Autodesk Fusion 360 part; units mm, degrees
(part 4 of 7)
sketch "New stock profile (42)" plane through (330.6, 0, 0) normal (1, 0, 0) x (0, 0, -1) in component "front right rail mount 1-1 weld boss"
  circle A0 centre (-84.1, -195.15) radius 6.5
  circle A1 centre (-84.1, -195.15) radius 2.5
extrude "New 1'''''''''''''''''''''''''''''''''''''''''" add sketch "New stock profile (42)" against normal blind 16 separate body makes body 168 in component "front right rail mount 1-1 weld boss"
ref_plane "WorkPlane1" through (328.5, 0, 0) normal (1, 0, 0) x (0, 1, 0) in component "front right rail mount 1-1 M6 cap screw"
sketch "New stock profile (43)" plane through (328.5, 0, 0) normal (1, 0, 0) x (0, 0, -1) in component "front right rail mount 1-1 M6 cap screw"
  circle A0 centre (-84.1, -195.15) radius 3
extrude "New 1''''''''''''''''''''''''''''''''''''''''''" add sketch "New stock profile (43)" against normal blind 40 separate body makes body 169 in component "front right rail mount 1-1 M6 cap screw"
ref_plane "WorkPlane2" through (288.5, 0, 0) normal (1, 0, 0) x (0, 1, 0) in component "front right rail mount 1-1 M6 cap screw"
sketch "Join stock profile (9)" plane through (288.5, 0, 0) normal (1, 0, 0) x (0, 0, -1) in component "front right rail mount 1-1 M6 cap screw"
  circle A0 centre (-84.1, -195.15) radius 5
extrude "Join 2''''''''" add sketch "Join stock profile (9)" against normal blind 6 bodies 169 in component "front right rail mount 1-1 M6 cap screw"
ref_plane "WorkPlane3" through (282.49, 0, 0) normal (1, 0, 0) x (0, 1, 0) in component "front right rail mount 1-1 M6 cap screw"
sketch "Cut stock profile (33)" plane through (282.49, 0, 0) normal (1, 0, 0) x (0, 0, -1) in component "front right rail mount 1-1 M6 cap screw"
  line L0 (-84.1, -192.2632) -> (-86.6, -193.7066)
  line L1 (-86.6, -193.7066) -> (-86.6, -196.5934)
  line L2 (-86.6, -196.5934) -> (-84.1, -198.0368)
  line L3 (-84.1, -198.0368) -> (-81.6, -196.5934)
  line L4 (-81.6, -196.5934) -> (-81.6, -193.7066)
  line L5 (-81.6, -193.7066) -> (-84.1, -192.2632)
extrude "Cut 3''''''''''''''''" cut sketch "Cut stock profile (33)" along normal blind 3.01 bodies 169 in component "front right rail mount 1-1 M6 cap screw"
ref_plane "WorkPlane1" through (330.6, 0, 0) normal (1, 0, 0) x (0, 1, 0) in component "front right rail mount 1-2 weld boss"
sketch "New stock profile (44)" plane through (330.6, 0, 0) normal (1, 0, 0) x (0, 0, -1) in component "front right rail mount 1-2 weld boss"
  circle A0 centre (-105.1, -195.15) radius 6.5
  circle A1 centre (-105.1, -195.15) radius 2.5
extrude "New 1'''''''''''''''''''''''''''''''''''''''''''" add sketch "New stock profile (44)" against normal blind 16 separate body makes body 170 in component "front right rail mount 1-2 weld boss"
ref_plane "WorkPlane1" through (328.5, 0, 0) normal (1, 0, 0) x (0, 1, 0) in component "front right rail mount 1-2 M6 cap screw"
sketch "New stock profile (45)" plane through (328.5, 0, 0) normal (1, 0, 0) x (0, 0, -1) in component "front right rail mount 1-2 M6 cap screw"
  circle A0 centre (-105.1, -195.15) radius 3
extrude "New 1''''''''''''''''''''''''''''''''''''''''''''" add sketch "New stock profile (45)" against normal blind 40 separate body makes body 171 in component "front right rail mount 1-2 M6 cap screw"
ref_plane "WorkPlane2" through (288.5, 0, 0) normal (1, 0, 0) x (0, 1, 0) in component "front right rail mount 1-2 M6 cap screw"
sketch "Join stock profile (10)" plane through (288.5, 0, 0) normal (1, 0, 0) x (0, 0, -1) in component "front right rail mount 1-2 M6 cap screw"
  circle A0 centre (-105.1, -195.15) radius 5
extrude "Join 2'''''''''" add sketch "Join stock profile (10)" against normal blind 6 bodies 171 in component "front right rail mount 1-2 M6 cap screw"
ref_plane "WorkPlane3" through (282.49, 0, 0) normal (1, 0, 0) x (0, 1, 0) in component "front right rail mount 1-2 M6 cap screw"
sketch "Cut stock profile (34)" plane through (282.49, 0, 0) normal (1, 0, 0) x (0, 0, -1) in component "front right rail mount 1-2 M6 cap screw"
  line L0 (-105.1, -192.2632) -> (-107.6, -193.7066)
  line L1 (-107.6, -193.7066) -> (-107.6, -196.5934)
  line L2 (-107.6, -196.5934) -> (-105.1, -198.0368)
  line L3 (-105.1, -198.0368) -> (-102.6, -196.5934)
  line L4 (-102.6, -196.5934) -> (-102.6, -193.7066)
  line L5 (-102.6, -193.7066) -> (-105.1, -192.2632)
extrude "Cut 3'''''''''''''''''" cut sketch "Cut stock profile (34)" along normal blind 3.01 bodies 171 in component "front right rail mount 1-2 M6 cap screw"
ref_plane "WorkPlane1" through (0, 0, 65.5637) normal (0, 0, 1) x (1, 0, 0) in component "front right tab 1-1 socket screw"
sketch "New stock profile (46)" plane through (0, 0, 65.5637) normal (0, 0, 1) x (1, 0, 0) in component "front right tab 1-1 socket screw"
  circle A0 centre (296.75, -207.85) radius 2.413
extrude "New 1'''''''''''''''''''''''''''''''''''''''''''''" add sketch "New stock profile (46)" along normal blind 69.85 separate body makes body 172 in component "front right tab 1-1 socket screw"
ref_plane "WorkPlane2" through (0, 0, 60.7378) normal (0, 0, 1) x (1, 0, 0) in component "front right tab 1-1 socket screw"
sketch "Join stock profile (11)" plane through (0, 0, 60.7378) normal (0, 0, 1) x (1, 0, 0) in component "front right tab 1-1 socket screw"
  circle A0 centre (296.75, -207.85) radius 3.9624
extrude "Join 2''''''''''" add sketch "Join stock profile (11)" along normal blind 4.826 bodies 172 in component "front right tab 1-1 socket screw"
ref_plane "WorkPlane3" through (0, 0, 60.7278) normal (0, 0, 1) x (1, 0, 0) in component "front right tab 1-1 socket screw"
sketch "Cut stock profile (35)" plane through (0, 0, 60.7278) normal (0, 0, 1) x (1, 0, 0) in component "front right tab 1-1 socket screw"
  line L0 (299.0414, -207.85) -> (297.8957, -205.8656)
  line L1 (297.8957, -205.8656) -> (295.6043, -205.8656)
  line L2 (295.6043, -205.8656) -> (294.4586, -207.85)
  line L3 (294.4586, -207.85) -> (295.6043, -209.8344)
  line L4 (295.6043, -209.8344) -> (297.8957, -209.8344)
  line L5 (297.8957, -209.8344) -> (299.0414, -207.85)
extrude "Cut 3''''''''''''''''''" cut sketch "Cut stock profile (35)" along normal blind 2.296 bodies 172 in component "front right tab 1-1 socket screw"
ref_plane "WorkPlane1" through (0, 0, 124.3125) normal (0, 0, 1) x (1, 0, 0) in component "front right tab 1-1 locknut"
sketch "New stock profile (47)" plane through (0, 0, 124.3125) normal (0, 0, 1) x (1, 0, 0) in component "front right tab 1-1 locknut"
  line L0 (302.2639, -207.85) -> (299.507, -203.0748)
  line L1 (299.507, -203.0748) -> (293.993, -203.0748)
  line L2 (293.993, -203.0748) -> (291.2361, -207.85)
  line L3 (291.2361, -207.85) -> (293.993, -212.6252)
  line L4 (293.993, -212.6252) -> (299.507, -212.6252)
  line L5 (299.507, -212.6252) -> (302.2639, -207.85)
  circle A0 centre (296.75, -207.85) radius 2.43
extrude "New 1''''''''''''''''''''''''''''''''''''''''''''''" add sketch "New stock profile (47)" along normal blind 6.3246 separate body makes body 173 in component "front right tab 1-1 locknut"
ref_plane "WorkPlane1" through (0, 0, 65.5637) normal (0, 0, 1) x (1, 0, 0) in component "front right tab 1-2 socket screw"
sketch "New stock profile (48)" plane through (0, 0, 65.5637) normal (0, 0, 1) x (1, 0, 0) in component "front right tab 1-2 socket screw"
  circle A0 centre (296.75, -182.45) radius 2.413
extrude "New 1'''''''''''''''''''''''''''''''''''''''''''''''" add sketch "New stock profile (48)" along normal blind 69.85 separate body makes body 174 in component "front right tab 1-2 socket screw"
ref_plane "WorkPlane2" through (0, 0, 60.7378) normal (0, 0, 1) x (1, 0, 0) in component "front right tab 1-2 socket screw"
sketch "Join stock profile (12)" plane through (0, 0, 60.7378) normal (0, 0, 1) x (1, 0, 0) in component "front right tab 1-2 socket screw"
  circle A0 centre (296.75, -182.45) radius 3.9624
extrude "Join 2'''''''''''" add sketch "Join stock profile (12)" along normal blind 4.826 bodies 174 in component "front right tab 1-2 socket screw"
ref_plane "WorkPlane3" through (0, 0, 60.7278) normal (0, 0, 1) x (1, 0, 0) in component "front right tab 1-2 socket screw"
sketch "Cut stock profile (36)" plane through (0, 0, 60.7278) normal (0, 0, 1) x (1, 0, 0) in component "front right tab 1-2 socket screw"
  line L0 (299.0414, -182.45) -> (297.8957, -180.4656)
  line L1 (297.8957, -180.4656) -> (295.6043, -180.4656)
  line L2 (295.6043, -180.4656) -> (294.4586, -182.45)
  line L3 (294.4586, -182.45) -> (295.6043, -184.4344)
  line L4 (295.6043, -184.4344) -> (297.8957, -184.4344)
  line L5 (297.8957, -184.4344) -> (299.0414, -182.45)
extrude "Cut 3'''''''''''''''''''" cut sketch "Cut stock profile (36)" along normal blind 2.296 bodies 174 in component "front right tab 1-2 socket screw"
ref_plane "WorkPlane1" through (0, 0, 124.3125) normal (0, 0, 1) x (1, 0, 0) in component "front right tab 1-2 locknut"
sketch "New stock profile (49)" plane through (0, 0, 124.3125) normal (0, 0, 1) x (1, 0, 0) in component "front right tab 1-2 locknut"
  line L0 (302.2639, -182.45) -> (299.507, -177.6748)
  line L1 (299.507, -177.6748) -> (293.993, -177.6748)
  line L2 (293.993, -177.6748) -> (291.2361, -182.45)
  line L3 (291.2361, -182.45) -> (293.993, -187.2252)
  line L4 (293.993, -187.2252) -> (299.507, -187.2252)
  line L5 (299.507, -187.2252) -> (302.2639, -182.45)
  circle A0 centre (296.75, -182.45) radius 2.43
extrude "New 1''''''''''''''''''''''''''''''''''''''''''''''''" add sketch "New stock profile (49)" along normal blind 6.3246 separate body makes body 175 in component "front right tab 1-2 locknut"
ref_plane "WorkPlane1" through (0, -330.6, 0) normal (0, 1, 0) x (0, 0, 1) in component "front right rail mount 2-1 weld boss"
sketch "New stock profile (50)" plane through (0, -330.6, 0) normal (0, 1, 0) x (1, 0, 0) in component "front right rail mount 2-1 weld boss"
  circle A0 centre (195.15, -84.1) radius 6.5
  circle A1 centre (195.15, -84.1) radius 2.5
extrude "New 1'''''''''''''''''''''''''''''''''''''''''''''''''" add sketch "New stock profile (50)" along normal blind 16 separate body makes body 176 in component "front right rail mount 2-1 weld boss"
ref_plane "WorkPlane1" through (0, -328.5, 0) normal (0, 1, 0) x (0, 0, 1) in component "front right rail mount 2-1 M6 cap screw"
sketch "New stock profile (51)" plane through (0, -328.5, 0) normal (0, 1, 0) x (1, 0, 0) in component "front right rail mount 2-1 M6 cap screw"
  circle A0 centre (195.15, -84.1) radius 3
extrude "New 1''''''''''''''''''''''''''''''''''''''''''''''''''" add sketch "New stock profile (51)" along normal blind 40 separate body makes body 177 in component "front right rail mount 2-1 M6 cap screw"
ref_plane "WorkPlane2" through (0, -288.5, 0) normal (0, 1, 0) x (0, 0, 1) in component "front right rail mount 2-1 M6 cap screw"
sketch "Join stock profile (13)" plane through (0, -288.5, 0) normal (0, 1, 0) x (1, 0, 0) in component "front right rail mount 2-1 M6 cap screw"
  circle A0 centre (195.15, -84.1) radius 5
extrude "Join 2''''''''''''" add sketch "Join stock profile (13)" along normal blind 6 bodies 177 in component "front right rail mount 2-1 M6 cap screw"
ref_plane "WorkPlane3" through (0, -282.49, 0) normal (0, 1, 0) x (0, 0, 1) in component "front right rail mount 2-1 M6 cap screw"
sketch "Cut stock profile (37)" plane through (0, -282.49, 0) normal (0, 1, 0) x (1, 0, 0) in component "front right rail mount 2-1 M6 cap screw"
  line L0 (198.0368, -84.1) -> (196.5934, -86.6)
  line L1 (196.5934, -86.6) -> (193.7066, -86.6)
  line L2 (193.7066, -86.6) -> (192.2632, -84.1)
  line L3 (192.2632, -84.1) -> (193.7066, -81.6)
  line L4 (193.7066, -81.6) -> (196.5934, -81.6)
  line L5 (196.5934, -81.6) -> (198.0368, -84.1)
extrude "Cut 3''''''''''''''''''''" cut sketch "Cut stock profile (37)" against normal blind 3.01 bodies 177 in component "front right rail mount 2-1 M6 cap screw"
ref_plane "WorkPlane1" through (0, -330.6, 0) normal (0, 1, 0) x (0, 0, 1) in component "front right rail mount 2-2 weld boss"
sketch "New stock profile (52)" plane through (0, -330.6, 0) normal (0, 1, 0) x (1, 0, 0) in component "front right rail mount 2-2 weld boss"
  circle A0 centre (195.15, -105.1) radius 6.5
  circle A1 centre (195.15, -105.1) radius 2.5
extrude "New 1'''''''''''''''''''''''''''''''''''''''''''''''''''" add sketch "New stock profile (52)" along normal blind 16 separate body makes body 178 in component "front right rail mount 2-2 weld boss"
ref_plane "WorkPlane1" through (0, -328.5, 0) normal (0, 1, 0) x (0, 0, 1) in component "front right rail mount 2-2 M6 cap screw"
sketch "New stock profile (53)" plane through (0, -328.5, 0) normal (0, 1, 0) x (1, 0, 0) in component "front right rail mount 2-2 M6 cap screw"
  circle A0 centre (195.15, -105.1) radius 3
extrude "New 1''''''''''''''''''''''''''''''''''''''''''''''''''''" add sketch "New stock profile (53)" along normal blind 40 separate body makes body 179 in component "front right rail mount 2-2 M6 cap screw"
ref_plane "WorkPlane2" through (0, -288.5, 0) normal (0, 1, 0) x (0, 0, 1) in component "front right rail mount 2-2 M6 cap screw"
sketch "Join stock profile (14)" plane through (0, -288.5, 0) normal (0, 1, 0) x (1, 0, 0) in component "front right rail mount 2-2 M6 cap screw"
  circle A0 centre (195.15, -105.1) radius 5
extrude "Join 2'''''''''''''" add sketch "Join stock profile (14)" along normal blind 6 bodies 179 in component "front right rail mount 2-2 M6 cap screw"
ref_plane "WorkPlane3" through (0, -282.49, 0) normal (0, 1, 0) x (0, 0, 1) in component "front right rail mount 2-2 M6 cap screw"
sketch "Cut stock profile (38)" plane through (0, -282.49, 0) normal (0, 1, 0) x (1, 0, 0) in component "front right rail mount 2-2 M6 cap screw"
  line L0 (198.0368, -105.1) -> (196.5934, -107.6)
  line L1 (196.5934, -107.6) -> (193.7066, -107.6)
  line L2 (193.7066, -107.6) -> (192.2632, -105.1)
  line L3 (192.2632, -105.1) -> (193.7066, -102.6)
  line L4 (193.7066, -102.6) -> (196.5934, -102.6)
  line L5 (196.5934, -102.6) -> (198.0368, -105.1)
extrude "Cut 3'''''''''''''''''''''" cut sketch "Cut stock profile (38)" against normal blind 3.01 bodies 179 in component "front right rail mount 2-2 M6 cap screw"
ref_plane "WorkPlane1" through (0, 0, 65.5637) normal (0, 0, 1) x (1, 0, 0) in component "front right tab 2-1 socket screw"
sketch "New stock profile (54)" plane through (0, 0, 65.5637) normal (0, 0, 1) x (1, 0, 0) in component "front right tab 2-1 socket screw"
  circle A0 centre (207.85, -296.75) radius 2.413
extrude "New 1'''''''''''''''''''''''''''''''''''''''''''''''''''''" add sketch "New stock profile (54)" along normal blind 69.85 separate body makes body 180 in component "front right tab 2-1 socket screw"
ref_plane "WorkPlane2" through (0, 0, 60.7378) normal (0, 0, 1) x (1, 0, 0) in component "front right tab 2-1 socket screw"
sketch "Join stock profile (15)" plane through (0, 0, 60.7378) normal (0, 0, 1) x (1, 0, 0) in component "front right tab 2-1 socket screw"
  circle A0 centre (207.85, -296.75) radius 3.9624
extrude "Join 2''''''''''''''" add sketch "Join stock profile (15)" along normal blind 4.826 bodies 180 in component "front right tab 2-1 socket screw"
ref_plane "WorkPlane3" through (0, 0, 60.7278) normal (0, 0, 1) x (1, 0, 0) in component "front right tab 2-1 socket screw"
sketch "Cut stock profile (39)" plane through (0, 0, 60.7278) normal (0, 0, 1) x (1, 0, 0) in component "front right tab 2-1 socket screw"
  line L0 (210.1414, -296.75) -> (208.9957, -294.7656)
  line L1 (208.9957, -294.7656) -> (206.7043, -294.7656)
  line L2 (206.7043, -294.7656) -> (205.5586, -296.75)
  line L3 (205.5586, -296.75) -> (206.7043, -298.7344)
  line L4 (206.7043, -298.7344) -> (208.9957, -298.7344)
  line L5 (208.9957, -298.7344) -> (210.1414, -296.75)
extrude "Cut 3''''''''''''''''''''''" cut sketch "Cut stock profile (39)" along normal blind 2.296 bodies 180 in component "front right tab 2-1 socket screw"
ref_plane "WorkPlane1" through (0, 0, 124.3125) normal (0, 0, 1) x (1, 0, 0) in component "front right tab 2-1 locknut"
sketch "New stock profile (55)" plane through (0, 0, 124.3125) normal (0, 0, 1) x (1, 0, 0) in component "front right tab 2-1 locknut"
  line L0 (213.3639, -296.75) -> (210.607, -291.9748)
  line L1 (210.607, -291.9748) -> (205.093, -291.9748)
  line L2 (205.093, -291.9748) -> (202.3361, -296.75)
  line L3 (202.3361, -296.75) -> (205.093, -301.5252)
  line L4 (205.093, -301.5252) -> (210.607, -301.5252)
  line L5 (210.607, -301.5252) -> (213.3639, -296.75)
  circle A0 centre (207.85, -296.75) radius 2.43
extrude "New 1''''''''''''''''''''''''''''''''''''''''''''''''''''''" add sketch "New stock profile (55)" along normal blind 6.3246 separate body makes body 181 in component "front right tab 2-1 locknut"
ref_plane "WorkPlane1" through (0, 0, 65.5637) normal (0, 0, 1) x (1, 0, 0) in component "front right tab 2-2 socket screw"
sketch "New stock profile (56)" plane through (0, 0, 65.5637) normal (0, 0, 1) x (1, 0, 0) in component "front right tab 2-2 socket screw"
  circle A0 centre (182.45, -296.75) radius 2.413
extrude "New 1'''''''''''''''''''''''''''''''''''''''''''''''''''''''" add sketch "New stock profile (56)" along normal blind 69.85 separate body makes body 182 in component "front right tab 2-2 socket screw"
ref_plane "WorkPlane2" through (0, 0, 60.7378) normal (0, 0, 1) x (1, 0, 0) in component "front right tab 2-2 socket screw"
sketch "Join stock profile (16)" plane through (0, 0, 60.7378) normal (0, 0, 1) x (1, 0, 0) in component "front right tab 2-2 socket screw"
  circle A0 centre (182.45, -296.75) radius 3.9624
extrude "Join 2'''''''''''''''" add sketch "Join stock profile (16)" along normal blind 4.826 bodies 182 in component "front right tab 2-2 socket screw"
ref_plane "WorkPlane3" through (0, 0, 60.7278) normal (0, 0, 1) x (1, 0, 0) in component "front right tab 2-2 socket screw"
sketch "Cut stock profile (40)" plane through (0, 0, 60.7278) normal (0, 0, 1) x (1, 0, 0) in component "front right tab 2-2 socket screw"
  line L0 (184.7414, -296.75) -> (183.5957, -294.7656)
  line L1 (183.5957, -294.7656) -> (181.3043, -294.7656)
  line L2 (181.3043, -294.7656) -> (180.1586, -296.75)
  line L3 (180.1586, -296.75) -> (181.3043, -298.7344)
  line L4 (181.3043, -298.7344) -> (183.5957, -298.7344)
  line L5 (183.5957, -298.7344) -> (184.7414, -296.75)
extrude "Cut 3'''''''''''''''''''''''" cut sketch "Cut stock profile (40)" along normal blind 2.296 bodies 182 in component "front right tab 2-2 socket screw"
ref_plane "WorkPlane1" through (0, 0, 124.3125) normal (0, 0, 1) x (1, 0, 0) in component "front right tab 2-2 locknut"
sketch "New stock profile (57)" plane through (0, 0, 124.3125) normal (0, 0, 1) x (1, 0, 0) in component "front right tab 2-2 locknut"
  line L0 (187.9639, -296.75) -> (185.207, -291.9748)
  line L1 (185.207, -291.9748) -> (179.693, -291.9748)
  line L2 (179.693, -291.9748) -> (176.9361, -296.75)
  line L3 (176.9361, -296.75) -> (179.693, -301.5252)
  line L4 (179.693, -301.5252) -> (185.207, -301.5252)
  line L5 (185.207, -301.5252) -> (187.9639, -296.75)
  circle A0 centre (182.45, -296.75) radius 2.43
extrude "New 1''''''''''''''''''''''''''''''''''''''''''''''''''''''''" add sketch "New stock profile (57)" along normal blind 6.3246 separate body makes body 183 in component "front right tab 2-2 locknut"
ref_plane "WorkPlane1" through (-330.6, 0, 0) normal (1, 0, 0) x (0, 1, 0) in component "rear left rail mount 1-1 weld boss"
sketch "New stock profile (58)" plane through (-330.6, 0, 0) normal (1, 0, 0) x (0, 0, -1) in component "rear left rail mount 1-1 weld boss"
  circle A0 centre (-84.1, 195.15) radius 6.5
  circle A1 centre (-84.1, 195.15) radius 2.5
extrude "New 1'''''''''''''''''''''''''''''''''''''''''''''''''''''''''" add sketch "New stock profile (58)" along normal blind 16 separate body makes body 184 in component "rear left rail mount 1-1 weld boss"
ref_plane "WorkPlane1" through (-328.5, 0, 0) normal (1, 0, 0) x (0, 1, 0) in component "rear left rail mount 1-1 M6 cap screw"
sketch "New stock profile (59)" plane through (-328.5, 0, 0) normal (1, 0, 0) x (0, 0, -1) in component "rear left rail mount 1-1 M6 cap screw"
  circle A0 centre (-84.1, 195.15) radius 3
extrude "New 1''''''''''''''''''''''''''''''''''''''''''''''''''''''''''" add sketch "New stock profile (59)" along normal blind 40 separate body makes body 185 in component "rear left rail mount 1-1 M6 cap screw"
ref_plane "WorkPlane2" through (-288.5, 0, 0) normal (1, 0, 0) x (0, 1, 0) in component "rear left rail mount 1-1 M6 cap screw"
sketch "Join stock profile (17)" plane through (-288.5, 0, 0) normal (1, 0, 0) x (0, 0, -1) in component "rear left rail mount 1-1 M6 cap screw"
  circle A0 centre (-84.1, 195.15) radius 5
extrude "Join 2''''''''''''''''" add sketch "Join stock profile (17)" along normal blind 6 bodies 185 in component "rear left rail mount 1-1 M6 cap screw"
ref_plane "WorkPlane3" through (-282.49, 0, 0) normal (1, 0, 0) x (0, 1, 0) in component "rear left rail mount 1-1 M6 cap screw"
sketch "Cut stock profile (41)" plane through (-282.49, 0, 0) normal (1, 0, 0) x (0, 0, -1) in component "rear left rail mount 1-1 M6 cap screw"
  line L0 (-84.1, 192.2632) -> (-86.6, 193.7066)
  line L1 (-86.6, 193.7066) -> (-86.6, 196.5934)
  line L2 (-86.6, 196.5934) -> (-84.1, 198.0368)
  line L3 (-84.1, 198.0368) -> (-81.6, 196.5934)
  line L4 (-81.6, 196.5934) -> (-81.6, 193.7066)
  line L5 (-81.6, 193.7066) -> (-84.1, 192.2632)
extrude "Cut 3''''''''''''''''''''''''" cut sketch "Cut stock profile (41)" against normal blind 3.01 bodies 185 in component "rear left rail mount 1-1 M6 cap screw"
ref_plane "WorkPlane1" through (-330.6, 0, 0) normal (1, 0, 0) x (0, 1, 0) in component "rear left rail mount 1-2 weld boss"
sketch "New stock profile (60)" plane through (-330.6, 0, 0) normal (1, 0, 0) x (0, 0, -1) in component "rear left rail mount 1-2 weld boss"
  circle A0 centre (-105.1, 195.15) radius 6.5
  circle A1 centre (-105.1, 195.15) radius 2.5
extrude "New 1'''''''''''''''''''''''''''''''''''''''''''''''''''''''''''" add sketch "New stock profile (60)" along normal blind 16 separate body makes body 186 in component "rear left rail mount 1-2 weld boss"
ref_plane "WorkPlane1" through (-328.5, 0, 0) normal (1, 0, 0) x (0, 1, 0) in component "rear left rail mount 1-2 M6 cap screw"
sketch "New stock profile (61)" plane through (-328.5, 0, 0) normal (1, 0, 0) x (0, 0, -1) in component "rear left rail mount 1-2 M6 cap screw"
  circle A0 centre (-105.1, 195.15) radius 3
extrude "New 1''''''''''''''''''''''''''''''''''''''''''''''''''''''''''''" add sketch "New stock profile (61)" along normal blind 40 separate body makes body 187 in component "rear left rail mount 1-2 M6 cap screw"
ref_plane "WorkPlane2" through (-288.5, 0, 0) normal (1, 0, 0) x (0, 1, 0) in component "rear left rail mount 1-2 M6 cap screw"
sketch "Join stock profile (18)" plane through (-288.5, 0, 0) normal (1, 0, 0) x (0, 0, -1) in component "rear left rail mount 1-2 M6 cap screw"
  circle A0 centre (-105.1, 195.15) radius 5
extrude "Join 2'''''''''''''''''" add sketch "Join stock profile (18)" along normal blind 6 bodies 187 in component "rear left rail mount 1-2 M6 cap screw"
ref_plane "WorkPlane3" through (-282.49, 0, 0) normal (1, 0, 0) x (0, 1, 0) in component "rear left rail mount 1-2 M6 cap screw"
sketch "Cut stock profile (42)" plane through (-282.49, 0, 0) normal (1, 0, 0) x (0, 0, -1) in component "rear left rail mount 1-2 M6 cap screw"
  line L0 (-105.1, 192.2632) -> (-107.6, 193.7066)
  line L1 (-107.6, 193.7066) -> (-107.6, 196.5934)
  line L2 (-107.6, 196.5934) -> (-105.1, 198.0368)
  line L3 (-105.1, 198.0368) -> (-102.6, 196.5934)
  line L4 (-102.6, 196.5934) -> (-102.6, 193.7066)
  line L5 (-102.6, 193.7066) -> (-105.1, 192.2632)
extrude "Cut 3'''''''''''''''''''''''''" cut sketch "Cut stock profile (42)" against normal blind 3.01 bodies 187 in component "rear left rail mount 1-2 M6 cap screw"
ref_plane "WorkPlane1" through (0, 0, 65.5637) normal (0, 0, 1) x (1, 0, 0) in component "rear left tab 1-1 socket screw"
sketch "New stock profile (62)" plane through (0, 0, 65.5637) normal (0, 0, 1) x (1, 0, 0) in component "rear left tab 1-1 socket screw"
  circle A0 centre (-296.75, 207.85) radius 2.413
extrude "New 1'''''''''''''''''''''''''''''''''''''''''''''''''''''''''''''" add sketch "New stock profile (62)" along normal blind 69.85 separate body makes body 188 in component "rear left tab 1-1 socket screw"
ref_plane "WorkPlane2" through (0, 0, 60.7378) normal (0, 0, 1) x (1, 0, 0) in component "rear left tab 1-1 socket screw"
sketch "Join stock profile (19)" plane through (0, 0, 60.7378) normal (0, 0, 1) x (1, 0, 0) in component "rear left tab 1-1 socket screw"
  circle A0 centre (-296.75, 207.85) radius 3.9624
extrude "Join 2''''''''''''''''''" add sketch "Join stock profile (19)" along normal blind 4.826 bodies 188 in component "rear left tab 1-1 socket screw"
ref_plane "WorkPlane3" through (0, 0, 60.7278) normal (0, 0, 1) x (1, 0, 0) in component "rear left tab 1-1 socket screw"
sketch "Cut stock profile (43)" plane through (0, 0, 60.7278) normal (0, 0, 1) x (1, 0, 0) in component "rear left tab 1-1 socket screw"
  line L0 (-294.4586, 207.85) -> (-295.6043, 209.8344)
  line L1 (-295.6043, 209.8344) -> (-297.8957, 209.8344)
  line L2 (-297.8957, 209.8344) -> (-299.0414, 207.85)
  line L3 (-299.0414, 207.85) -> (-297.8957, 205.8656)
  line L4 (-297.8957, 205.8656) -> (-295.6043, 205.8656)
  line L5 (-295.6043, 205.8656) -> (-294.4586, 207.85)
extrude "Cut 3''''''''''''''''''''''''''" cut sketch "Cut stock profile (43)" along normal blind 2.296 bodies 188 in component "rear left tab 1-1 socket screw"
ref_plane "WorkPlane1" through (0, 0, 124.3125) normal (0, 0, 1) x (1, 0, 0) in component "rear left tab 1-1 locknut"
sketch "New stock profile (63)" plane through (0, 0, 124.3125) normal (0, 0, 1) x (1, 0, 0) in component "rear left tab 1-1 locknut"
  line L0 (-291.2361, 207.85) -> (-293.993, 212.6252)
  line L1 (-293.993, 212.6252) -> (-299.507, 212.6252)
  line L2 (-299.507, 212.6252) -> (-302.2639, 207.85)
  line L3 (-302.2639, 207.85) -> (-299.507, 203.0748)
  line L4 (-299.507, 203.0748) -> (-293.993, 203.0748)
  line L5 (-293.993, 203.0748) -> (-291.2361, 207.85)
  circle A0 centre (-296.75, 207.85) radius 2.43
extrude "New 1''''''''''''''''''''''''''''''''''''''''''''''''''''''''''''''" add sketch "New stock profile (63)" along normal blind 6.3246 separate body makes body 189 in component "rear left tab 1-1 locknut"
ref_plane "WorkPlane1" through (0, 0, 65.5637) normal (0, 0, 1) x (1, 0, 0) in component "rear left tab 1-2 socket screw"
sketch "New stock profile (64)" plane through (0, 0, 65.5637) normal (0, 0, 1) x (1, 0, 0) in component "rear left tab 1-2 socket screw"
  circle A0 centre (-296.75, 182.45) radius 2.413
extrude "New 1'''''''''''''''''''''''''''''''''''''''''''''''''''''''''''''''" add sketch "New stock profile (64)" along normal blind 69.85 separate body makes body 190 in component "rear left tab 1-2 socket screw"
ref_plane "WorkPlane2" through (0, 0, 60.7378) normal (0, 0, 1) x (1, 0, 0) in component "rear left tab 1-2 socket screw"
sketch "Join stock profile (20)" plane through (0, 0, 60.7378) normal (0, 0, 1) x (1, 0, 0) in component "rear left tab 1-2 socket screw"
  circle A0 centre (-296.75, 182.45) radius 3.9624
extrude "Join 2'''''''''''''''''''" add sketch "Join stock profile (20)" along normal blind 4.826 bodies 190 in component "rear left tab 1-2 socket screw"
ref_plane "WorkPlane3" through (0, 0, 60.7278) normal (0, 0, 1) x (1, 0, 0) in component "rear left tab 1-2 socket screw"
sketch "Cut stock profile (44)" plane through (0, 0, 60.7278) normal (0, 0, 1) x (1, 0, 0) in component "rear left tab 1-2 socket screw"
  line L0 (-294.4586, 182.45) -> (-295.6043, 184.4344)
  line L1 (-295.6043, 184.4344) -> (-297.8957, 184.4344)
  line L2 (-297.8957, 184.4344) -> (-299.0414, 182.45)
  line L3 (-299.0414, 182.45) -> (-297.8957, 180.4656)
  line L4 (-297.8957, 180.4656) -> (-295.6043, 180.4656)
  line L5 (-295.6043, 180.4656) -> (-294.4586, 182.45)
extrude "Cut 3'''''''''''''''''''''''''''" cut sketch "Cut stock profile (44)" along normal blind 2.296 bodies 190 in component "rear left tab 1-2 socket screw"
ref_plane "WorkPlane1" through (0, 0, 124.3125) normal (0, 0, 1) x (1, 0, 0) in component "rear left tab 1-2 locknut"
sketch "New stock profile (65)" plane through (0, 0, 124.3125) normal (0, 0, 1) x (1, 0, 0) in component "rear left tab 1-2 locknut"
  line L0 (-291.2361, 182.45) -> (-293.993, 187.2252)
  line L1 (-293.993, 187.2252) -> (-299.507, 187.2252)
  line L2 (-299.507, 187.2252) -> (-302.2639, 182.45)
  line L3 (-302.2639, 182.45) -> (-299.507, 177.6748)
  line L4 (-299.507, 177.6748) -> (-293.993, 177.6748)
  line L5 (-293.993, 177.6748) -> (-291.2361, 182.45)
  circle A0 centre (-296.75, 182.45) radius 2.43
extrude "New 1''''''''''''''''''''''''''''''''''''''''''''''''''''''''''''''''" add sketch "New stock profile (65)" along normal blind 6.3246 separate body makes body 191 in component "rear left tab 1-2 locknut"
ref_plane "WorkPlane1" through (0, 330.6, 0) normal (0, 1, 0) x (0, 0, 1) in component "rear left rail mount 2-1 weld boss"
sketch "New stock profile (66)" plane through (0, 330.6, 0) normal (0, 1, 0) x (1, 0, 0) in component "rear left rail mount 2-1 weld boss"
  circle A0 centre (-195.15, -84.1) radius 6.5
  circle A1 centre (-195.15, -84.1) radius 2.5
extrude "New 1'''''''''''''''''''''''''''''''''''''''''''''''''''''''''''''''''" add sketch "New stock profile (66)" against normal blind 16 separate body makes body 192 in component "rear left rail mount 2-1 weld boss"
ref_plane "WorkPlane1" through (0, 328.5, 0) normal (0, 1, 0) x (0, 0, 1) in component "rear left rail mount 2-1 M6 cap screw"
sketch "New stock profile (67)" plane through (0, 328.5, 0) normal (0, 1, 0) x (1, 0, 0) in component "rear left rail mount 2-1 M6 cap screw"
  circle A0 centre (-195.15, -84.1) radius 3
extrude "New 1''''''''''''''''''''''''''''''''''''''''''''''''''''''''''''''''''" add sketch "New stock profile (67)" against normal blind 40 separate body makes body 193 in component "rear left rail mount 2-1 M6 cap screw"
ref_plane "WorkPlane2" through (0, 288.5, 0) normal (0, 1, 0) x (0, 0, 1) in component "rear left rail mount 2-1 M6 cap screw"
sketch "Join stock profile (21)" plane through (0, 288.5, 0) normal (0, 1, 0) x (1, 0, 0) in component "rear left rail mount 2-1 M6 cap screw"
  circle A0 centre (-195.15, -84.1) radius 5
extrude "Join 2''''''''''''''''''''" add sketch "Join stock profile (21)" against normal blind 6 bodies 193 in component "rear left rail mount 2-1 M6 cap screw"
ref_plane "WorkPlane3" through (0, 282.49, 0) normal (0, 1, 0) x (0, 0, 1) in component "rear left rail mount 2-1 M6 cap screw"
sketch "Cut stock profile (45)" plane through (0, 282.49, 0) normal (0, 1, 0) x (1, 0, 0) in component "rear left rail mount 2-1 M6 cap screw"
  line L0 (-198.0368, -84.1) -> (-196.5934, -86.6)
  line L1 (-196.5934, -86.6) -> (-193.7066, -86.6)
  line L2 (-193.7066, -86.6) -> (-192.2632, -84.1)
  line L3 (-192.2632, -84.1) -> (-193.7066, -81.6)
  line L4 (-193.7066, -81.6) -> (-196.5934, -81.6)
  line L5 (-196.5934, -81.6) -> (-198.0368, -84.1)
extrude "Cut 3''''''''''''''''''''''''''''" cut sketch "Cut stock profile (45)" along normal blind 3.01 bodies 193 in component "rear left rail mount 2-1 M6 cap screw"
ref_plane "WorkPlane1" through (0, 330.6, 0) normal (0, 1, 0) x (0, 0, 1) in component "rear left rail mount 2-2 weld boss"
sketch "New stock profile (68)" plane through (0, 330.6, 0) normal (0, 1, 0) x (1, 0, 0) in component "rear left rail mount 2-2 weld boss"
  circle A0 centre (-195.15, -105.1) radius 6.5
  circle A1 centre (-195.15, -105.1) radius 2.5
extrude "New 1'''''''''''''''''''''''''''''''''''''''''''''''''''''''''''''''''''" add sketch "New stock profile (68)" against normal blind 16 separate body makes body 194 in component "rear left rail mount 2-2 weld boss"
ref_plane "WorkPlane1" through (0, 328.5, 0) normal (0, 1, 0) x (0, 0, 1) in component "rear left rail mount 2-2 M6 cap screw"
sketch "New stock profile (69)" plane through (0, 328.5, 0) normal (0, 1, 0) x (1, 0, 0) in component "rear left rail mount 2-2 M6 cap screw"
  circle A0 centre (-195.15, -105.1) radius 3
extrude "New 1''''''''''''''''''''''''''''''''''''''''''''''''''''''''''''''''''''" add sketch "New stock profile (69)" against normal blind 40 separate body makes body 195 in component "rear left rail mount 2-2 M6 cap screw"
ref_plane "WorkPlane2" through (0, 288.5, 0) normal (0, 1, 0) x (0, 0, 1) in component "rear left rail mount 2-2 M6 cap screw"
sketch "Join stock profile (22)" plane through (0, 288.5, 0) normal (0, 1, 0) x (1, 0, 0) in component "rear left rail mount 2-2 M6 cap screw"
  circle A0 centre (-195.15, -105.1) radius 5
extrude "Join 2'''''''''''''''''''''" add sketch "Join stock profile (22)" against normal blind 6 bodies 195 in component "rear left rail mount 2-2 M6 cap screw"
ref_plane "WorkPlane3" through (0, 282.49, 0) normal (0, 1, 0) x (0, 0, 1) in component "rear left rail mount 2-2 M6 cap screw"
sketch "Cut stock profile (46)" plane through (0, 282.49, 0) normal (0, 1, 0) x (1, 0, 0) in component "rear left rail mount 2-2 M6 cap screw"
  line L0 (-198.0368, -105.1) -> (-196.5934, -107.6)
  line L1 (-196.5934, -107.6) -> (-193.7066, -107.6)
  line L2 (-193.7066, -107.6) -> (-192.2632, -105.1)
  line L3 (-192.2632, -105.1) -> (-193.7066, -102.6)
  line L4 (-193.7066, -102.6) -> (-196.5934, -102.6)
  line L5 (-196.5934, -102.6) -> (-198.0368, -105.1)
extrude "Cut 3'''''''''''''''''''''''''''''" cut sketch "Cut stock profile (46)" along normal blind 3.01 bodies 195 in component "rear left rail mount 2-2 M6 cap screw"
ref_plane "WorkPlane1" through (0, 0, 65.5637) normal (0, 0, 1) x (1, 0, 0) in component "rear left tab 2-1 socket screw"
sketch "New stock profile (70)" plane through (0, 0, 65.5637) normal (0, 0, 1) x (1, 0, 0) in component "rear left tab 2-1 socket screw"
  circle A0 centre (-207.85, 296.75) radius 2.413
extrude "New 1'''''''''''''''''''''''''''''''''''''''''''''''''''''''''''''''''''''" add sketch "New stock profile (70)" along normal blind 69.85 separate body makes body 196 in component "rear left tab 2-1 socket screw"
ref_plane "WorkPlane2" through (0, 0, 60.7378) normal (0, 0, 1) x (1, 0, 0) in component "rear left tab 2-1 socket screw"
sketch "Join stock profile (23)" plane through (0, 0, 60.7378) normal (0, 0, 1) x (1, 0, 0) in component "rear left tab 2-1 socket screw"
  circle A0 centre (-207.85, 296.75) radius 3.9624
extrude "Join 2''''''''''''''''''''''" add sketch "Join stock profile (23)" along normal blind 4.826 bodies 196 in component "rear left tab 2-1 socket screw"
ref_plane "WorkPlane3" through (0, 0, 60.7278) normal (0, 0, 1) x (1, 0, 0) in component "rear left tab 2-1 socket screw"
sketch "Cut stock profile (47)" plane through (0, 0, 60.7278) normal (0, 0, 1) x (1, 0, 0) in component "rear left tab 2-1 socket screw"
  line L0 (-205.5586, 296.75) -> (-206.7043, 298.7344)
  line L1 (-206.7043, 298.7344) -> (-208.9957, 298.7344)
  line L2 (-208.9957, 298.7344) -> (-210.1414, 296.75)
  line L3 (-210.1414, 296.75) -> (-208.9957, 294.7656)
  line L4 (-208.9957, 294.7656) -> (-206.7043, 294.7656)
  line L5 (-206.7043, 294.7656) -> (-205.5586, 296.75)
extrude "Cut 3''''''''''''''''''''''''''''''" cut sketch "Cut stock profile (47)" along normal blind 2.296 bodies 196 in component "rear left tab 2-1 socket screw"
ref_plane "WorkPlane1" through (0, 0, 124.3125) normal (0, 0, 1) x (1, 0, 0) in component "rear left tab 2-1 locknut"
sketch "New stock profile (71)" plane through (0, 0, 124.3125) normal (0, 0, 1) x (1, 0, 0) in component "rear left tab 2-1 locknut"
  line L0 (-202.3361, 296.75) -> (-205.093, 301.5252)
  line L1 (-205.093, 301.5252) -> (-210.607, 301.5252)
  line L2 (-210.607, 301.5252) -> (-213.3639, 296.75)
  line L3 (-213.3639, 296.75) -> (-210.607, 291.9748)
  line L4 (-210.607, 291.9748) -> (-205.093, 291.9748)
  line L5 (-205.093, 291.9748) -> (-202.3361, 296.75)
  circle A0 centre (-207.85, 296.75) radius 2.43
extrude "New 1''''''''''''''''''''''''''''''''''''''''''''''''''''''''''''''''''''''" add sketch "New stock profile (71)" along normal blind 6.3246 separate body makes body 197 in component "rear left tab 2-1 locknut"
ref_plane "WorkPlane1" through (0, 0, 65.5637) normal (0, 0, 1) x (1, 0, 0) in component "rear left tab 2-2 socket screw"
sketch "New stock profile (72)" plane through (0, 0, 65.5637) normal (0, 0, 1) x (1, 0, 0) in component "rear left tab 2-2 socket screw"
  circle A0 centre (-182.45, 296.75) radius 2.413
extrude "New 1'''''''''''''''''''''''''''''''''''''''''''''''''''''''''''''''''''''''" add sketch "New stock profile (72)" along normal blind 69.85 separate body makes body 198 in component "rear left tab 2-2 socket screw"
ref_plane "WorkPlane2" through (0, 0, 60.7378) normal (0, 0, 1) x (1, 0, 0) in component "rear left tab 2-2 socket screw"
sketch "Join stock profile (24)" plane through (0, 0, 60.7378) normal (0, 0, 1) x (1, 0, 0) in component "rear left tab 2-2 socket screw"
  circle A0 centre (-182.45, 296.75) radius 3.9624
extrude "Join 2'''''''''''''''''''''''" add sketch "Join stock profile (24)" along normal blind 4.826 bodies 198 in component "rear left tab 2-2 socket screw"
ref_plane "WorkPlane3" through (0, 0, 60.7278) normal (0, 0, 1) x (1, 0, 0) in component "rear left tab 2-2 socket screw"
sketch "Cut stock profile (48)" plane through (0, 0, 60.7278) normal (0, 0, 1) x (1, 0, 0) in component "rear left tab 2-2 socket screw"
  line L0 (-180.1586, 296.75) -> (-181.3043, 298.7344)
  line L1 (-181.3043, 298.7344) -> (-183.5957, 298.7344)
  line L2 (-183.5957, 298.7344) -> (-184.7414, 296.75)
  line L3 (-184.7414, 296.75) -> (-183.5957, 294.7656)
  line L4 (-183.5957, 294.7656) -> (-181.3043, 294.7656)
  line L5 (-181.3043, 294.7656) -> (-180.1586, 296.75)
extrude "Cut 3'''''''''''''''''''''''''''''''" cut sketch "Cut stock profile (48)" along normal blind 2.296 bodies 198 in component "rear left tab 2-2 socket screw"
ref_plane "WorkPlane1" through (0, 0, 124.3125) normal (0, 0, 1) x (1, 0, 0) in component "rear left tab 2-2 locknut"
sketch "New stock profile (73)" plane through (0, 0, 124.3125) normal (0, 0, 1) x (1, 0, 0) in component "rear left tab 2-2 locknut"
  line L0 (-176.9361, 296.75) -> (-179.693, 301.5252)
  line L1 (-179.693, 301.5252) -> (-185.207, 301.5252)
  line L2 (-185.207, 301.5252) -> (-187.9639, 296.75)
  line L3 (-187.9639, 296.75) -> (-185.207, 291.9748)
  line L4 (-185.207, 291.9748) -> (-179.693, 291.9748)
  line L5 (-179.693, 291.9748) -> (-176.9361, 296.75)
  circle A0 centre (-182.45, 296.75) radius 2.43
extrude "New 1''''''''''''''''''''''''''''''''''''''''''''''''''''''''''''''''''''''''" add sketch "New stock profile (73)" along normal blind 6.3246 separate body makes body 199 in component "rear left tab 2-2 locknut"
ref_plane "WorkPlane1" through (0, -330.6, 0) normal (0, 1, 0) x (0, 0, 1) in component "rear right rail mount 1-1 weld boss"
sketch "New stock profile (74)" plane through (0, -330.6, 0) normal (0, 1, 0) x (1, 0, 0) in component "rear right rail mount 1-1 weld boss"
  circle A0 centre (-195.15, -84.1) radius 6.5
  circle A1 centre (-195.15, -84.1) radius 2.5
extrude "New 1'''''''''''''''''''''''''''''''''''''''''''''''''''''''''''''''''''''''''" add sketch "New stock profile (74)" along normal blind 16 separate body makes body 200 in component "rear right rail mount 1-1 weld boss"
ref_plane "WorkPlane1" through (0, -328.5, 0) normal (0, 1, 0) x (0, 0, 1) in component "rear right rail mount 1-1 M6 cap screw"
sketch "New stock profile (75)" plane through (0, -328.5, 0) normal (0, 1, 0) x (1, 0, 0) in component "rear right rail mount 1-1 M6 cap screw"
  circle A0 centre (-195.15, -84.1) radius 3
extrude "New 1''''''''''''''''''''''''''''''''''''''''''''''''''''''''''''''''''''''''''" add sketch "New stock profile (75)" along normal blind 40 separate body makes body 201 in component "rear right rail mount 1-1 M6 cap screw"
ref_plane "WorkPlane2" through (0, -288.5, 0) normal (0, 1, 0) x (0, 0, 1) in component "rear right rail mount 1-1 M6 cap screw"
sketch "Join stock profile (25)" plane through (0, -288.5, 0) normal (0, 1, 0) x (1, 0, 0) in component "rear right rail mount 1-1 M6 cap screw"
  circle A0 centre (-195.15, -84.1) radius 5
extrude "Join 2''''''''''''''''''''''''" add sketch "Join stock profile (25)" along normal blind 6 bodies 201 in component "rear right rail mount 1-1 M6 cap screw"
ref_plane "WorkPlane3" through (0, -282.49, 0) normal (0, 1, 0) x (0, 0, 1) in component "rear right rail mount 1-1 M6 cap screw"
sketch "Cut stock profile (49)" plane through (0, -282.49, 0) normal (0, 1, 0) x (1, 0, 0) in component "rear right rail mount 1-1 M6 cap screw"
  line L0 (-192.2632, -84.1) -> (-193.7066, -86.6)
  line L1 (-193.7066, -86.6) -> (-196.5934, -86.6)
  line L2 (-196.5934, -86.6) -> (-198.0368, -84.1)
  line L3 (-198.0368, -84.1) -> (-196.5934, -81.6)
  line L4 (-196.5934, -81.6) -> (-193.7066, -81.6)
  line L5 (-193.7066, -81.6) -> (-192.2632, -84.1)
extrude "Cut 3''''''''''''''''''''''''''''''''" cut sketch "Cut stock profile (49)" against normal blind 3.01 bodies 201 in component "rear right rail mount 1-1 M6 cap screw"
ref_plane "WorkPlane1" through (0, -330.6, 0) normal (0, 1, 0) x (0, 0, 1) in component "rear right rail mount 1-2 weld boss"
sketch "New stock profile (76)" plane through (0, -330.6, 0) normal (0, 1, 0) x (1, 0, 0) in component "rear right rail mount 1-2 weld boss"
  circle A0 centre (-195.15, -105.1) radius 6.5
  circle A1 centre (-195.15, -105.1) radius 2.5
extrude "New 1'''''''''''''''''''''''''''''''''''''''''''''''''''''''''''''''''''''''''''" add sketch "New stock profile (76)" along normal blind 16 separate body makes body 202 in component "rear right rail mount 1-2 weld boss"
ref_plane "WorkPlane1" through (0, -328.5, 0) normal (0, 1, 0) x (0, 0, 1) in component "rear right rail mount 1-2 M6 cap screw"
sketch "New stock profile (77)" plane through (0, -328.5, 0) normal (0, 1, 0) x (1, 0, 0) in component "rear right rail mount 1-2 M6 cap screw"
  circle A0 centre (-195.15, -105.1) radius 3
extrude "New 1''''''''''''''''''''''''''''''''''''''''''''''''''''''''''''''''''''''''''''" add sketch "New stock profile (77)" along normal blind 40 separate body makes body 203 in component "rear right rail mount 1-2 M6 cap screw"
ref_plane "WorkPlane2" through (0, -288.5, 0) normal (0, 1, 0) x (0, 0, 1) in component "rear right rail mount 1-2 M6 cap screw"
sketch "Join stock profile (26)" plane through (0, -288.5, 0) normal (0, 1, 0) x (1, 0, 0) in component "rear right rail mount 1-2 M6 cap screw"
  circle A0 centre (-195.15, -105.1) radius 5
extrude "Join 2'''''''''''''''''''''''''" add sketch "Join stock profile (26)" along normal blind 6 bodies 203 in component "rear right rail mount 1-2 M6 cap screw"
ref_plane "WorkPlane3" through (0, -282.49, 0) normal (0, 1, 0) x (0, 0, 1) in component "rear right rail mount 1-2 M6 cap screw"
sketch "Cut stock profile (50)" plane through (0, -282.49, 0) normal (0, 1, 0) x (1, 0, 0) in component "rear right rail mount 1-2 M6 cap screw"
  line L0 (-192.2632, -105.1) -> (-193.7066, -107.6)
  line L1 (-193.7066, -107.6) -> (-196.5934, -107.6)
  line L2 (-196.5934, -107.6) -> (-198.0368, -105.1)
  line L3 (-198.0368, -105.1) -> (-196.5934, -102.6)
  line L4 (-196.5934, -102.6) -> (-193.7066, -102.6)
  line L5 (-193.7066, -102.6) -> (-192.2632, -105.1)
extrude "Cut 3'''''''''''''''''''''''''''''''''" cut sketch "Cut stock profile (50)" against normal blind 3.01 bodies 203 in component "rear right rail mount 1-2 M6 cap screw"
ref_plane "WorkPlane1" through (0, 0, 65.5637) normal (0, 0, 1) x (1, 0, 0) in component "rear right tab 1-1 socket screw"
sketch "New stock profile (78)" plane through (0, 0, 65.5637) normal (0, 0, 1) x (1, 0, 0) in component "rear right tab 1-1 socket screw"
  circle A0 centre (-207.85, -296.75) radius 2.413
extrude "New 1'''''''''''''''''''''''''''''''''''''''''''''''''''''''''''''''''''''''''''''" add sketch "New stock profile (78)" along normal blind 69.85 separate body makes body 204 in component "rear right tab 1-1 socket screw"
ref_plane "WorkPlane2" through (0, 0, 60.7378) normal (0, 0, 1) x (1, 0, 0) in component "rear right tab 1-1 socket screw"
sketch "Join stock profile (27)" plane through (0, 0, 60.7378) normal (0, 0, 1) x (1, 0, 0) in component "rear right tab 1-1 socket screw"
  circle A0 centre (-207.85, -296.75) radius 3.9624
extrude "Join 2''''''''''''''''''''''''''" add sketch "Join stock profile (27)" along normal blind 4.826 bodies 204 in component "rear right tab 1-1 socket screw"
ref_plane "WorkPlane3" through (0, 0, 60.7278) normal (0, 0, 1) x (1, 0, 0) in component "rear right tab 1-1 socket screw"
sketch "Cut stock profile (51)" plane through (0, 0, 60.7278) normal (0, 0, 1) x (1, 0, 0) in component "rear right tab 1-1 socket screw"
  line L0 (-205.5586, -296.75) -> (-206.7043, -294.7656)
  line L1 (-206.7043, -294.7656) -> (-208.9957, -294.7656)
  line L2 (-208.9957, -294.7656) -> (-210.1414, -296.75)
  line L3 (-210.1414, -296.75) -> (-208.9957, -298.7344)
  line L4 (-208.9957, -298.7344) -> (-206.7043, -298.7344)
  line L5 (-206.7043, -298.7344) -> (-205.5586, -296.75)
extrude "Cut 3''''''''''''''''''''''''''''''''''" cut sketch "Cut stock profile (51)" along normal blind 2.296 bodies 204 in component "rear right tab 1-1 socket screw"
ref_plane "WorkPlane1" through (0, 0, 124.3125) normal (0, 0, 1) x (1, 0, 0) in component "rear right tab 1-1 locknut"
sketch "New stock profile (79)" plane through (0, 0, 124.3125) normal (0, 0, 1) x (1, 0, 0) in component "rear right tab 1-1 locknut"
  line L0 (-202.3361, -296.75) -> (-205.093, -291.9748)
  line L1 (-205.093, -291.9748) -> (-210.607, -291.9748)
  line L2 (-210.607, -291.9748) -> (-213.3639, -296.75)
  line L3 (-213.3639, -296.75) -> (-210.607, -301.5252)
  line L4 (-210.607, -301.5252) -> (-205.093, -301.5252)
  line L5 (-205.093, -301.5252) -> (-202.3361, -296.75)
  circle A0 centre (-207.85, -296.75) radius 2.43
extrude "New 1''''''''''''''''''''''''''''''''''''''''''''''''''''''''''''''''''''''''''''''" add sketch "New stock profile (79)" along normal blind 6.3246 separate body makes body 205 in component "rear right tab 1-1 locknut"
ref_plane "WorkPlane1" through (0, 0, 65.5637) normal (0, 0, 1) x (1, 0, 0) in component "rear right tab 1-2 socket screw"
sketch "New stock profile (80)" plane through (0, 0, 65.5637) normal (0, 0, 1) x (1, 0, 0) in component "rear right tab 1-2 socket screw"
  circle A0 centre (-182.45, -296.75) radius 2.413
extrude "New 1'''''''''''''''''''''''''''''''''''''''''''''''''''''''''''''''''''''''''''''''" add sketch "New stock profile (80)" along normal blind 69.85 separate body makes body 206 in component "rear right tab 1-2 socket screw"
ref_plane "WorkPlane2" through (0, 0, 60.7378) normal (0, 0, 1) x (1, 0, 0) in component "rear right tab 1-2 socket screw"
sketch "Join stock profile (28)" plane through (0, 0, 60.7378) normal (0, 0, 1) x (1, 0, 0) in component "rear right tab 1-2 socket screw"
  circle A0 centre (-182.45, -296.75) radius 3.9624
extrude "Join 2'''''''''''''''''''''''''''" add sketch "Join stock profile (28)" along normal blind 4.826 bodies 206 in component "rear right tab 1-2 socket screw"
ref_plane "WorkPlane3" through (0, 0, 60.7278) normal (0, 0, 1) x (1, 0, 0) in component "rear right tab 1-2 socket screw"
sketch "Cut stock profile (52)" plane through (0, 0, 60.7278) normal (0, 0, 1) x (1, 0, 0) in component "rear right tab 1-2 socket screw"
  line L0 (-180.1586, -296.75) -> (-181.3043, -294.7656)
  line L1 (-181.3043, -294.7656) -> (-183.5957, -294.7656)
  line L2 (-183.5957, -294.7656) -> (-184.7414, -296.75)
  line L3 (-184.7414, -296.75) -> (-183.5957, -298.7344)
  line L4 (-183.5957, -298.7344) -> (-181.3043, -298.7344)
  line L5 (-181.3043, -298.7344) -> (-180.1586, -296.75)
extrude "Cut 3'''''''''''''''''''''''''''''''''''" cut sketch "Cut stock profile (52)" along normal blind 2.296 bodies 206 in component "rear right tab 1-2 socket screw"
ref_plane "WorkPlane1" through (0, 0, 124.3125) normal (0, 0, 1) x (1, 0, 0) in component "rear right tab 1-2 locknut"
sketch "New stock profile (81)" plane through (0, 0, 124.3125) normal (0, 0, 1) x (1, 0, 0) in component "rear right tab 1-2 locknut"
  line L0 (-176.9361, -296.75) -> (-179.693, -291.9748)
  line L1 (-179.693, -291.9748) -> (-185.207, -291.9748)
  line L2 (-185.207, -291.9748) -> (-187.9639, -296.75)
  line L3 (-187.9639, -296.75) -> (-185.207, -301.5252)
  line L4 (-185.207, -301.5252) -> (-179.693, -301.5252)
  line L5 (-179.693, -301.5252) -> (-176.9361, -296.75)
  circle A0 centre (-182.45, -296.75) radius 2.43
extrude "New 1''''''''''''''''''''''''''''''''''''''''''''''''''''''''''''''''''''''''''''''''" add sketch "New stock profile (81)" along normal blind 6.3246 separate body makes body 207 in component "rear right tab 1-2 locknut"
ref_plane "WorkPlane1" through (-330.6, 0, 0) normal (1, 0, 0) x (0, 1, 0) in component "rear right rail mount 2-1 weld boss"
sketch "New stock profile (82)" plane through (-330.6, 0, 0) normal (1, 0, 0) x (0, 0, -1) in component "rear right rail mount 2-1 weld boss"
  circle A0 centre (-84.1, -195.15) radius 6.5
  circle A1 centre (-84.1, -195.15) radius 2.5
extrude "New 1'''''''''''''''''''''''''''''''''''''''''''''''''''''''''''''''''''''''''''''''''" add sketch "New stock profile (82)" along normal blind 16 separate body makes body 208 in component "rear right rail mount 2-1 weld boss"